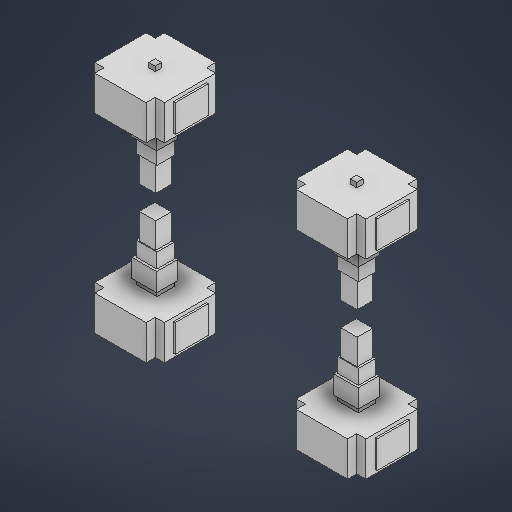
# Autodesk Inventor part: 02_Cum_4_Banh_Mecanum80_Va_Motor_1_90
Saved by Autodesk Inventor 2027.1 (Build 311270010, 270A)
## iProperties
Created: 2026-11-18
Part Number: 02_Cum_4_Banh_Mecanum80_Va_Motor_1_90
Material: Generic
Document SubType Name: Modeling
Designer: cuong
Density: 1 g/cm^3
Appearance: Default
Author: cuong
Autodesk Inventor part; units mm, degrees
ref_plane "Work Plane1" through (0, 0, 30.6) normal (0, 0, 1) x (1, 0, 0)
sketch "Sketch1" plane through (0, 0, 30.6) normal (0, 0, 1) x (1, 0, 0)
  line L0 (53.75, 42) -> (76.25, 42)
  line L1 (76.25, 42) -> (76.25, 84)
  line L2 (76.25, 84) -> (53.75, 84)
  line L3 (53.75, 84) -> (53.75, 42)
  constraints: 8 end point, 2 parallel, 1 horizontal, 1 perpendicular
extrude "Extrusion1" add sketch "Sketch1" along normal blind 18.8
ref_plane "Work Plane2" through (0, 0, 31.5) normal (0, 0, 1) x (1, 0, 0)
sketch "Sketch2" plane through (0, 0, 31.5) normal (0, 0, 1) x (1, 0, 0)
  line L0 (56, 84) -> (74, 84)
  line L1 (74, 84) -> (74, 112)
  line L2 (74, 112) -> (56, 112)
  line L3 (56, 112) -> (56, 84)
  constraints: 8 end point, 2 parallel, 1 horizontal, 1 perpendicular
extrude "Extrusion2" add sketch "Sketch2" along normal blind 17
ref_plane "Work Plane3" through (0, 0, 29) normal (0, 0, 1) x (1, 0, 0)
sketch "Sketch3" plane through (0, 0, 29) normal (0, 0, 1) x (1, 0, 0)
  line L0 (51.5, 48) -> (78.5, 48)
  line L1 (78.5, 48) -> (78.5, 68)
  line L2 (78.5, 68) -> (51.5, 68)
  line L3 (51.5, 68) -> (51.5, 48)
  constraints: 8 end point, 2 parallel, 1 horizontal, 1 perpendicular
extrude "Extrusion3" add sketch "Sketch3" along normal blind 23
ref_plane "Work Plane4" through (0, 0, 12) normal (0, 0, 1) x (1, 0, 0)
sketch "Sketch4" plane through (0, 0, 12) normal (0, 0, 1) x (1, 0, 0)
  line L0 (27, 2) -> (103, 2)
  line L1 (103, 2) -> (103, 40)
  line L2 (103, 40) -> (27, 40)
  line L3 (27, 40) -> (27, 2)
  constraints: 8 end point, 2 parallel, 1 horizontal, 1 perpendicular
extrude "Extrusion4" add sketch "Sketch4" along normal blind 56
ref_plane "Work Plane5" through (0, 0, 2) normal (0, 0, 1) x (1, 0, 0)
sketch "Sketch5" plane through (0, 0, 2) normal (0, 0, 1) x (1, 0, 0)
  line L0 (37, 2) -> (93, 2)
  line L1 (93, 2) -> (93, 40)
  line L2 (93, 40) -> (37, 40)
  line L3 (37, 40) -> (37, 2)
  constraints: 8 end point, 2 parallel, 1 horizontal, 1 perpendicular
extrude "Extrusion5" add sketch "Sketch5" along normal blind 76
ref_plane "Work Plane6" through (0, 0, 22) normal (0, 0, 1) x (1, 0, 0)
sketch "Sketch6" plane through (0, 0, 22) normal (0, 0, 1) x (1, 0, 0)
  line L0 (25, 6) -> (105, 6)
  line L1 (105, 6) -> (105, 36)
  line L2 (105, 36) -> (25, 36)
  line L3 (25, 36) -> (25, 6)
  constraints: 8 end point, 2 parallel, 1 horizontal, 1 perpendicular
extrude "Extrusion6" add sketch "Sketch6" along normal blind 36
ref_plane "Work Plane7" through (0, 0, 36.5) normal (0, 0, 1) x (1, 0, 0)
sketch "Sketch7" plane through (0, 0, 36.5) normal (0, 0, 1) x (1, 0, 0)
  line L0 (61.5, -3) -> (68.5, -3)
  line L1 (68.5, -3) -> (68.5, 45)
  line L2 (68.5, 45) -> (61.5, 45)
  line L3 (61.5, 45) -> (61.5, -3)
  constraints: 8 end point, 2 parallel, 1 horizontal, 1 perpendicular
extrude "Extrusion7" add sketch "Sketch7" along normal blind 7
ref_plane "Work Plane8" through (0, 0, 30.6) normal (0, 0, 1) x (1, 0, 0)
sketch "Sketch8" plane through (0, 0, 30.6) normal (0, 0, 1) x (1, 0, 0)
  line L0 (53.75, 166) -> (76.25, 166)
  line L1 (76.25, 166) -> (76.25, 208)
  line L2 (76.25, 208) -> (53.75, 208)
  line L3 (53.75, 208) -> (53.75, 166)
  constraints: 8 end point, 2 parallel, 1 horizontal, 1 perpendicular
extrude "Extrusion8" add sketch "Sketch8" along normal blind 18.8
ref_plane "Work Plane9" through (0, 0, 31.5) normal (0, 0, 1) x (1, 0, 0)
sketch "Sketch9" plane through (0, 0, 31.5) normal (0, 0, 1) x (1, 0, 0)
  line L0 (56, 138) -> (74, 138)
  line L1 (74, 138) -> (74, 166)
  line L2 (74, 166) -> (56, 166)
  line L3 (56, 166) -> (56, 138)
  constraints: 8 end point, 2 parallel, 1 horizontal, 1 perpendicular
extrude "Extrusion9" add sketch "Sketch9" along normal blind 17
ref_plane "Work Plane10" through (0, 0, 29) normal (0, 0, 1) x (1, 0, 0)
sketch "Sketch10" plane through (0, 0, 29) normal (0, 0, 1) x (1, 0, 0)
  line L0 (51.5, 182) -> (78.5, 182)
  line L1 (78.5, 182) -> (78.5, 202)
  line L2 (78.5, 202) -> (51.5, 202)
  line L3 (51.5, 202) -> (51.5, 182)
  constraints: 8 end point, 2 parallel, 1 horizontal, 1 perpendicular
extrude "Extrusion10" add sketch "Sketch10" along normal blind 23
ref_plane "Work Plane11" through (0, 0, 12) normal (0, 0, 1) x (1, 0, 0)
sketch "Sketch11" plane through (0, 0, 12) normal (0, 0, 1) x (1, 0, 0)
  line L0 (27, 210) -> (103, 210)
  line L1 (103, 210) -> (103, 248)
  line L2 (103, 248) -> (27, 248)
  line L3 (27, 248) -> (27, 210)
  constraints: 8 end point, 2 parallel, 1 horizontal, 1 perpendicular
extrude "Extrusion11" add sketch "Sketch11" along normal blind 56
ref_plane "Work Plane12" through (0, 0, 2) normal (0, 0, 1) x (1, 0, 0)
sketch "Sketch12" plane through (0, 0, 2) normal (0, 0, 1) x (1, 0, 0)
  line L0 (37, 210) -> (93, 210)
  line L1 (93, 210) -> (93, 248)
  line L2 (93, 248) -> (37, 248)
  line L3 (37, 248) -> (37, 210)
  constraints: 8 end point, 2 parallel, 1 horizontal, 1 perpendicular
extrude "Extrusion12" add sketch "Sketch12" along normal blind 76
ref_plane "Work Plane13" through (0, 0, 22) normal (0, 0, 1) x (1, 0, 0)
sketch "Sketch13" plane through (0, 0, 22) normal (0, 0, 1) x (1, 0, 0)
  line L0 (25, 214) -> (105, 214)
  line L1 (105, 214) -> (105, 244)
  line L2 (105, 244) -> (25, 244)
  line L3 (25, 244) -> (25, 214)
  constraints: 8 end point, 2 parallel, 1 horizontal, 1 perpendicular
extrude "Extrusion13" add sketch "Sketch13" along normal blind 36
ref_plane "Work Plane14" through (0, 0, 36.5) normal (0, 0, 1) x (1, 0, 0)
sketch "Sketch14" plane through (0, 0, 36.5) normal (0, 0, 1) x (1, 0, 0)
  line L0 (61.5, 205) -> (68.5, 205)
  line L1 (68.5, 205) -> (68.5, 253)
  line L2 (68.5, 253) -> (61.5, 253)
  line L3 (61.5, 253) -> (61.5, 205)
  constraints: 8 end point, 2 parallel, 1 horizontal, 1 perpendicular
extrude "Extrusion14" add sketch "Sketch14" along normal blind 7
ref_plane "Work Plane15" through (0, 0, 30.6) normal (0, 0, 1) x (1, 0, 0)
sketch "Sketch15" plane through (0, 0, 30.6) normal (0, 0, 1) x (1, 0, 0)
  line L0 (273.75, 42) -> (296.25, 42)
  line L1 (296.25, 42) -> (296.25, 84)
  line L2 (296.25, 84) -> (273.75, 84)
  line L3 (273.75, 84) -> (273.75, 42)
  constraints: 8 end point, 2 parallel, 1 horizontal, 1 perpendicular
extrude "Extrusion15" add sketch "Sketch15" along normal blind 18.8
ref_plane "Work Plane16" through (0, 0, 31.5) normal (0, 0, 1) x (1, 0, 0)
sketch "Sketch16" plane through (0, 0, 31.5) normal (0, 0, 1) x (1, 0, 0)
  line L0 (276, 84) -> (294, 84)
  line L1 (294, 84) -> (294, 112)
  line L2 (294, 112) -> (276, 112)
  line L3 (276, 112) -> (276, 84)
  constraints: 8 end point, 2 parallel, 1 horizontal, 1 perpendicular
extrude "Extrusion16" add sketch "Sketch16" along normal blind 17
ref_plane "Work Plane17" through (0, 0, 29) normal (0, 0, 1) x (1, 0, 0)
sketch "Sketch17" plane through (0, 0, 29) normal (0, 0, 1) x (1, 0, 0)
  line L0 (271.5, 48) -> (298.5, 48)
  line L1 (298.5, 48) -> (298.5, 68)
  line L2 (298.5, 68) -> (271.5, 68)
  line L3 (271.5, 68) -> (271.5, 48)
  constraints: 8 end point, 2 parallel, 1 horizontal, 1 perpendicular
extrude "Extrusion17" add sketch "Sketch17" along normal blind 23
ref_plane "Work Plane18" through (0, 0, 12) normal (0, 0, 1) x (1, 0, 0)
sketch "Sketch18" plane through (0, 0, 12) normal (0, 0, 1) x (1, 0, 0)
  line L0 (247, 2) -> (323, 2)
  line L1 (323, 2) -> (323, 40)
  line L2 (323, 40) -> (247, 40)
  line L3 (247, 40) -> (247, 2)
  constraints: 8 end point, 2 parallel, 1 horizontal, 1 perpendicular
extrude "Extrusion18" add sketch "Sketch18" along normal blind 56
ref_plane "Work Plane19" through (0, 0, 2) normal (0, 0, 1) x (1, 0, 0)
sketch "Sketch19" plane through (0, 0, 2) normal (0, 0, 1) x (1, 0, 0)
  line L0 (257, 2) -> (313, 2)
  line L1 (313, 2) -> (313, 40)
  line L2 (313, 40) -> (257, 40)
  line L3 (257, 40) -> (257, 2)
  constraints: 8 end point, 2 parallel, 1 horizontal, 1 perpendicular
extrude "Extrusion19" add sketch "Sketch19" along normal blind 76
ref_plane "Work Plane20" through (0, 0, 22) normal (0, 0, 1) x (1, 0, 0)
sketch "Sketch20" plane through (0, 0, 22) normal (0, 0, 1) x (1, 0, 0)
  line L0 (245, 6) -> (325, 6)
  line L1 (325, 6) -> (325, 36)
  line L2 (325, 36) -> (245, 36)
  line L3 (245, 36) -> (245, 6)
  constraints: 8 end point, 2 parallel, 1 horizontal, 1 perpendicular
extrude "Extrusion20" add sketch "Sketch20" along normal blind 36
ref_plane "Work Plane21" through (0, 0, 36.5) normal (0, 0, 1) x (1, 0, 0)
sketch "Sketch21" plane through (0, 0, 36.5) normal (0, 0, 1) x (1, 0, 0)
  line L0 (281.5, -3) -> (288.5, -3)
  line L1 (288.5, -3) -> (288.5, 45)
  line L2 (288.5, 45) -> (281.5, 45)
  line L3 (281.5, 45) -> (281.5, -3)
  constraints: 8 end point, 2 parallel, 1 horizontal, 1 perpendicular
extrude "Extrusion21" add sketch "Sketch21" along normal blind 7
ref_plane "Work Plane22" through (0, 0, 30.6) normal (0, 0, 1) x (1, 0, 0)
sketch "Sketch22" plane through (0, 0, 30.6) normal (0, 0, 1) x (1, 0, 0)
  line L0 (273.75, 166) -> (296.25, 166)
  line L1 (296.25, 166) -> (296.25, 208)
  line L2 (296.25, 208) -> (273.75, 208)
  line L3 (273.75, 208) -> (273.75, 166)
  constraints: 8 end point, 2 parallel, 1 horizontal, 1 perpendicular
extrude "Extrusion22" add sketch "Sketch22" along normal blind 18.8
ref_plane "Work Plane23" through (0, 0, 31.5) normal (0, 0, 1) x (1, 0, 0)
sketch "Sketch23" plane through (0, 0, 31.5) normal (0, 0, 1) x (1, 0, 0)
  line L0 (276, 138) -> (294, 138)
  line L1 (294, 138) -> (294, 166)
  line L2 (294, 166) -> (276, 166)
  line L3 (276, 166) -> (276, 138)
  constraints: 8 end point, 2 parallel, 1 horizontal, 1 perpendicular
extrude "Extrusion23" add sketch "Sketch23" along normal blind 17
ref_plane "Work Plane24" through (0, 0, 29) normal (0, 0, 1) x (1, 0, 0)
sketch "Sketch24" plane through (0, 0, 29) normal (0, 0, 1) x (1, 0, 0)
  line L0 (271.5, 182) -> (298.5, 182)
  line L1 (298.5, 182) -> (298.5, 202)
  line L2 (298.5, 202) -> (271.5, 202)
  line L3 (271.5, 202) -> (271.5, 182)
  constraints: 8 end point, 2 parallel, 1 horizontal, 1 perpendicular
extrude "Extrusion24" add sketch "Sketch24" along normal blind 23
ref_plane "Work Plane25" through (0, 0, 12) normal (0, 0, 1) x (1, 0, 0)
sketch "Sketch25" plane through (0, 0, 12) normal (0, 0, 1) x (1, 0, 0)
  line L0 (247, 210) -> (323, 210)
  line L1 (323, 210) -> (323, 248)
  line L2 (323, 248) -> (247, 248)
  line L3 (247, 248) -> (247, 210)
  constraints: 8 end point, 2 parallel, 1 horizontal, 1 perpendicular
extrude "Extrusion25" add sketch "Sketch25" along normal blind 56
ref_plane "Work Plane26" through (0, 0, 2) normal (0, 0, 1) x (1, 0, 0)
sketch "Sketch26" plane through (0, 0, 2) normal (0, 0, 1) x (1, 0, 0)
  line L0 (257, 210) -> (313, 210)
  line L1 (313, 210) -> (313, 248)
  line L2 (313, 248) -> (257, 248)
  line L3 (257, 248) -> (257, 210)
  constraints: 8 end point, 2 parallel, 1 horizontal, 1 perpendicular
extrude "Extrusion26" add sketch "Sketch26" along normal blind 76
ref_plane "Work Plane27" through (0, 0, 22) normal (0, 0, 1) x (1, 0, 0)
sketch "Sketch27" plane through (0, 0, 22) normal (0, 0, 1) x (1, 0, 0)
  line L0 (245, 214) -> (325, 214)
  line L1 (325, 214) -> (325, 244)
  line L2 (325, 244) -> (245, 244)
  line L3 (245, 244) -> (245, 214)
  constraints: 8 end point, 2 parallel, 1 horizontal, 1 perpendicular
extrude "Extrusion27" add sketch "Sketch27" along normal blind 36
ref_plane "Work Plane28" through (0, 0, 36.5) normal (0, 0, 1) x (1, 0, 0)
sketch "Sketch28" plane through (0, 0, 36.5) normal (0, 0, 1) x (1, 0, 0)
  line L0 (281.5, 205) -> (288.5, 205)
  line L1 (288.5, 205) -> (288.5, 253)
  line L2 (288.5, 253) -> (281.5, 253)
  line L3 (281.5, 253) -> (281.5, 205)
  constraints: 8 end point, 2 parallel, 1 horizontal, 1 perpendicular
extrude "Extrusion28" add sketch "Sketch28" along normal blind 7
body "Solid1"
